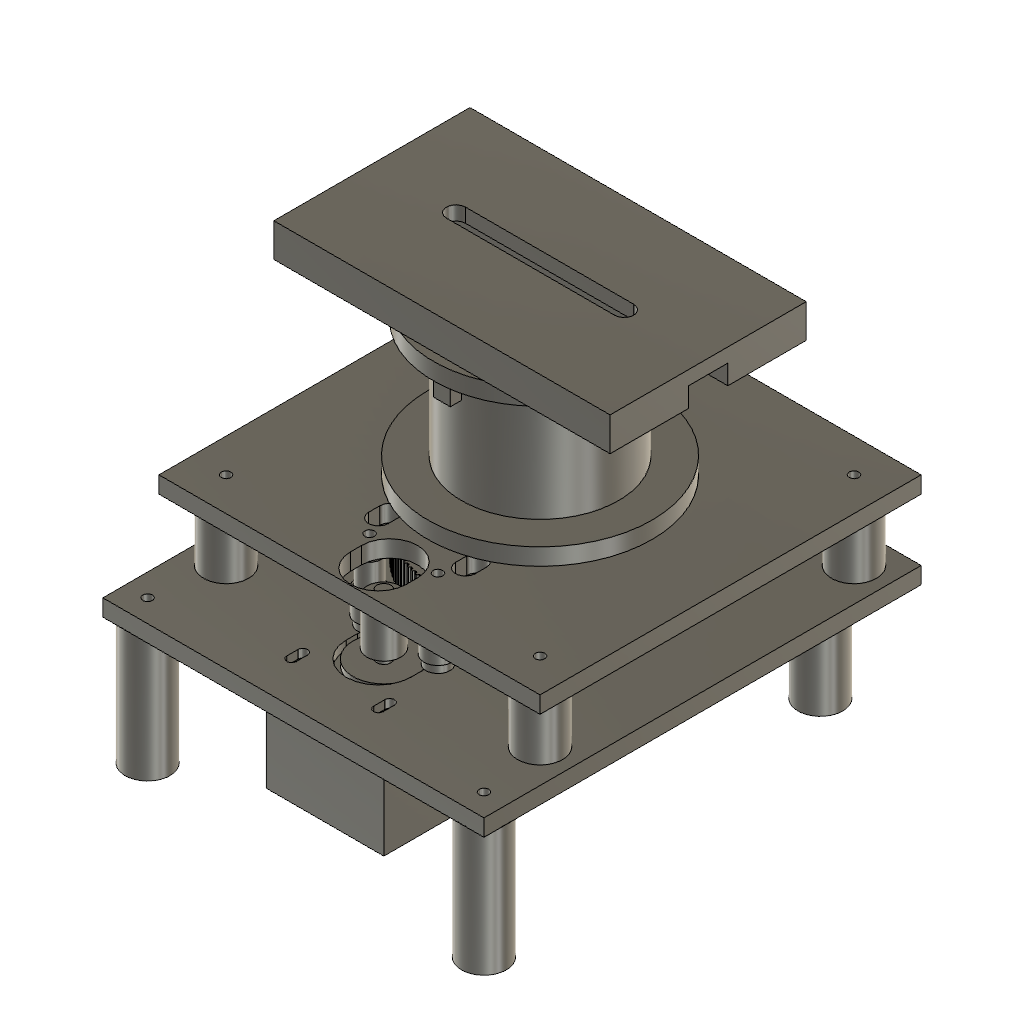
rig (Autodesk Fusion 360 design; units mm, degrees)
part number: 2026-11-04-20-32-03-425
part number: 2026-11-04-21-29-09-329
part number: 2026-11-04-21-29-10-710
part number: 2026-11-04-21-29-11-793
part number: 2026-11-04-21-29-12-270
part number: 2026-11-04-21-29-12-707
part number: 2026-11-04-21-29-14-277
part number: 2026-11-04-21-29-16-163
part number: 2026-11-04-21-29-17-402
part number: 2026-11-04-21-29-18-820
part number: 2026-11-04-21-29-20-301
part number: 2026-11-04-21-29-21-113
part number: 2026-11-04-21-29-36-706
part number: 2026-11-04-21-29-53-141
part number: 2026-11-04-21-29-54-485
part number: 2026-11-04-21-29-56-474
part number: 2026-11-04-21-29-57-771
part number: 2026-11-04-21-29-59-751
part number: 2026-11-04-21-30-00-972
part number: 2026-11-04-21-30-02-569
part number: 2026-11-04-21-30-03-701
part number: 2026-11-04-21-30-04-882
part number: 2026-11-04-21-30-06-087
Autodesk Fusion 360 part; units mm, degrees
(part 1 of 3)
ref_plane "WorkPlane1" through (0, 0, 0) normal (0, 0, 1) x (1, 0, 0) in component "print_bottom_plate"
sketch "Sketch1" plane through (0, 0, 0) normal (0, 0, 1) x (1, 0, 0) in component "print_bottom_plate"
  line L0 (-68, -88) -> (68, -88)
  line L1 (68, -88) -> (68, 68)
  line L2 (68, 68) -> (-68, 68)
  line L3 (-68, 68) -> (-68, -88)
extrude "Extrude1" add sketch "Sketch1" along normal blind 6 makes body 1 in component "print_bottom_plate"
ref_plane "WorkPlane2" through (0, 0, 0) normal (0, 0, 1) x (1, 0, 0) in component "print_bottom_plate"
sketch "Sketch2" plane through (0, 0, 0) normal (0, 0, 1) x (1, 0, 0) in component "print_bottom_plate"
  circle A0 centre (0, 0) radius 22
extrude "Extrude2" cut sketch "Sketch2" along normal blind 6 bodies 1 in component "print_bottom_plate"
ref_plane "WorkPlane3" through (0, 0, 0) normal (0, 0, 1) x (1, 0, 0) in component "print_bottom_plate"
sketch "Sketch3" plane through (0, 0, 0) normal (0, 0, 1) x (1, 0, 0) in component "print_bottom_plate"
  line L0 (-21.5, -79.15) -> (21.5, -79.15)
  line L1 (21.5, -79.15) -> (21.5, -32.15)
  line L2 (21.5, -32.15) -> (-21.5, -32.15)
  line L3 (-21.5, -32.15) -> (-21.5, -79.15)
extrude "Extrude3" cut sketch "Sketch3" along normal blind 3 bodies 1 in component "print_bottom_plate"
ref_plane "WorkPlane4" through (0, 0, 3) normal (0, 0, 1) x (1, 0, 0) in component "print_bottom_plate"
sketch "Sketch4" plane through (0, 0, 3) normal (0, 0, 1) x (1, 0, 0) in component "print_bottom_plate"
  circle A0 centre (0, -57.65) radius 11.5
  circle A1 centre (0, -53.65) radius 11.5
  line L0 (-11.5, -57.65) -> (11.5, -57.65)
  line L1 (11.5, -57.65) -> (11.5, -53.65)
  line L2 (11.5, -53.65) -> (-11.5, -53.65)
  line L3 (-11.5, -53.65) -> (-11.5, -57.65)
extrude "Extrude4" cut sketch "Sketch4" along normal blind 3 bodies 1 in component "print_bottom_plate"
ref_plane "WorkPlane5" through (0, 0, 3) normal (0, 0, 1) x (1, 0, 0) in component "print_bottom_plate"
sketch "Sketch5" plane through (0, 0, 3) normal (0, 0, 1) x (1, 0, 0) in component "print_bottom_plate"
  circle A0 centre (-15.5, -73.15) radius 1.7
  circle A1 centre (-15.5, -69.15) radius 1.7
  line L0 (-17.2, -73.15) -> (-13.8, -73.15)
  line L1 (-13.8, -73.15) -> (-13.8, -69.15)
  line L2 (-13.8, -69.15) -> (-17.2, -69.15)
  line L3 (-17.2, -69.15) -> (-17.2, -73.15)
extrude "Extrude5" cut sketch "Sketch5" along normal blind 3 bodies 1 in component "print_bottom_plate"
ref_plane "WorkPlane6" through (0, 0, 3) normal (0, 0, 1) x (1, 0, 0) in component "print_bottom_plate"
sketch "Sketch6" plane through (0, 0, 3) normal (0, 0, 1) x (1, 0, 0) in component "print_bottom_plate"
  circle A0 centre (-15.5, -42.15) radius 1.7
  circle A1 centre (-15.5, -38.15) radius 1.7
  line L0 (-17.2, -42.15) -> (-13.8, -42.15)
  line L1 (-13.8, -42.15) -> (-13.8, -38.15)
  line L2 (-13.8, -38.15) -> (-17.2, -38.15)
  line L3 (-17.2, -38.15) -> (-17.2, -42.15)
extrude "Extrude6" cut sketch "Sketch6" along normal blind 3 bodies 1 in component "print_bottom_plate"
ref_plane "WorkPlane7" through (0, 0, 3) normal (0, 0, 1) x (1, 0, 0) in component "print_bottom_plate"
sketch "Sketch7" plane through (0, 0, 3) normal (0, 0, 1) x (1, 0, 0) in component "print_bottom_plate"
  circle A0 centre (15.5, -73.15) radius 1.7
  circle A1 centre (15.5, -69.15) radius 1.7
  line L0 (13.8, -73.15) -> (17.2, -73.15)
  line L1 (17.2, -73.15) -> (17.2, -69.15)
  line L2 (17.2, -69.15) -> (13.8, -69.15)
  line L3 (13.8, -69.15) -> (13.8, -73.15)
extrude "Extrude7" cut sketch "Sketch7" along normal blind 3 bodies 1 in component "print_bottom_plate"
ref_plane "WorkPlane8" through (0, 0, 3) normal (0, 0, 1) x (1, 0, 0) in component "print_bottom_plate"
sketch "Sketch8" plane through (0, 0, 3) normal (0, 0, 1) x (1, 0, 0) in component "print_bottom_plate"
  circle A0 centre (15.5, -42.15) radius 1.7
  circle A1 centre (15.5, -38.15) radius 1.7
  line L0 (13.8, -42.15) -> (17.2, -42.15)
  line L1 (17.2, -42.15) -> (17.2, -38.15)
  line L2 (17.2, -38.15) -> (13.8, -38.15)
  line L3 (13.8, -38.15) -> (13.8, -42.15)
extrude "Extrude8" cut sketch "Sketch8" along normal blind 3 bodies 1 in component "print_bottom_plate"
ref_plane "WorkPlane9" through (0, 0, 0) normal (0, 0, 1) x (1, 0, 0) in component "print_bottom_plate"
sketch "Sketch9" plane through (0, 0, 0) normal (0, 0, 1) x (1, 0, 0) in component "print_bottom_plate"
  circle A0 centre (-56, 56) radius 1.7
  circle A1 centre (56, 56) radius 1.7
  circle A2 centre (56, -56) radius 1.7
  circle A3 centre (-56, -56) radius 1.7
  circle A4 centre (-60, -80) radius 1.7
  circle A5 centre (60, -80) radius 1.7
  circle A6 centre (40, 60) radius 1.7
  circle A7 centre (-40, 60) radius 1.7
extrude "Extrude9" cut sketch "Sketch9" along normal blind 6 bodies 1 in component "print_bottom_plate"
ref_plane "WorkPlane10" through (0, 0, 0) normal (0, 0, 1) x (1, 0, 0) in component "print_bottom_plate"
sketch "Sketch10" plane through (0, 0, 0) normal (0, 0, 1) x (1, 0, 0) in component "print_bottom_plate"
  circle A0 centre (-25, -25) radius 2
  circle A1 centre (-25, 25) radius 2
  circle A2 centre (25, -25) radius 2
  circle A3 centre (25, 25) radius 2
extrude "Extrude10" cut sketch "Sketch10" along normal blind 5 bodies 1 in component "print_bottom_plate"
ref_plane "WorkPlane11" through (0, 0, 3) normal (0, 0, 1) x (1, 0, 0) in component "print_bottom_plate"
sketch "Sketch11" plane through (0, 0, 3) normal (0, 0, 1) x (1, 0, 0) in component "print_bottom_plate"
  circle A0 centre (-12.2, -48.6) radius 1.7
  circle A1 centre (12.2, -48.6) radius 1.7
extrude "Extrude11" cut sketch "Sketch11" along normal blind 3 bodies 1 in component "print_bottom_plate"
ref_plane "WorkPlane1" through (0, 0, 28) normal (0, 0, 1) x (1, 0, 0) in component "print_top_plate"
sketch "Sketch1 (2)" plane through (0, 0, 28) normal (0, 0, 1) x (1, 0, 0) in component "print_top_plate"
  line L0 (-68, -68) -> (68, -68)
  line L1 (68, -68) -> (68, 68)
  line L2 (68, 68) -> (-68, 68)
  line L3 (-68, 68) -> (-68, -68)
extrude "Extrude1'" add sketch "Sketch1 (2)" along normal blind 6 separate body makes body 2 in component "print_top_plate"
ref_plane "WorkPlane2" through (0, 0, 28) normal (0, 0, 1) x (1, 0, 0) in component "print_top_plate"
sketch "Sketch2 (2)" plane through (0, 0, 28) normal (0, 0, 1) x (1, 0, 0) in component "print_top_plate"
  circle A0 centre (0, 0) radius 19.5
extrude "Extrude2'" cut sketch "Sketch2 (2)" along normal blind 6 bodies 2 in component "print_top_plate"
ref_plane "WorkPlane3" through (0, 0, 28) normal (0, 0, 1) x (1, 0, 0) in component "print_top_plate"
sketch "Sketch3 (2)" plane through (0, 0, 28) normal (0, 0, 1) x (1, 0, 0) in component "print_top_plate"
  circle A0 centre (-56, 56) radius 1.7
  circle A1 centre (56, 56) radius 1.7
  circle A2 centre (56, -56) radius 1.7
  circle A3 centre (-56, -56) radius 1.7
  circle A4 centre (-12.2, -48.6) radius 1.7
  circle A5 centre (12.2, -48.6) radius 1.7
  circle A6 centre (25.4558, 25.4558) radius 1.7
  circle A7 centre (-25.4558, 25.4558) radius 1.7
  circle A8 centre (-25.4558, -25.4558) radius 1.7
  circle A9 centre (25.4558, -25.4558) radius 1.7
extrude "Extrude3'" cut sketch "Sketch3 (2)" along normal blind 6 bodies 2 in component "print_top_plate"
ref_plane "WorkPlane4" through (0, 0, 28) normal (0, 0, 1) x (1, 0, 0) in component "print_top_plate"
sketch "Sketch4 (2)" plane through (0, 0, 28) normal (0, 0, 1) x (1, 0, 0) in component "print_top_plate"
  circle A0 centre (0, -57.65) radius 10
  circle A1 centre (0, -53.65) radius 10
  line L0 (-10, -57.65) -> (10, -57.65)
  line L1 (10, -57.65) -> (10, -53.65)
  line L2 (10, -53.65) -> (-10, -53.65)
  line L3 (-10, -53.65) -> (-10, -57.65)
extrude "Extrude4'" cut sketch "Sketch4 (2)" along normal blind 6 bodies 2 in component "print_top_plate"
ref_plane "WorkPlane5" through (0, 0, 28) normal (0, 0, 1) x (1, 0, 0) in component "print_top_plate"
sketch "Sketch5 (2)" plane through (0, 0, 28) normal (0, 0, 1) x (1, 0, 0) in component "print_top_plate"
  circle A0 centre (-15.5, -42.15) radius 3.5
  circle A1 centre (-15.5, -38.15) radius 3.5
  line L0 (-19, -42.15) -> (-12, -42.15)
  line L1 (-12, -42.15) -> (-12, -38.15)
  line L2 (-12, -38.15) -> (-19, -38.15)
  line L3 (-19, -38.15) -> (-19, -42.15)
extrude "Extrude5'" cut sketch "Sketch5 (2)" along normal blind 6 bodies 2 in component "print_top_plate"
ref_plane "WorkPlane6" through (0, 0, 28) normal (0, 0, 1) x (1, 0, 0) in component "print_top_plate"
sketch "Sketch6 (2)" plane through (0, 0, 28) normal (0, 0, 1) x (1, 0, 0) in component "print_top_plate"
  circle A0 centre (15.5, -42.15) radius 3.5
  circle A1 centre (15.5, -38.15) radius 3.5
  line L0 (12, -42.15) -> (19, -42.15)
  line L1 (19, -42.15) -> (19, -38.15)
  line L2 (19, -38.15) -> (12, -38.15)
  line L3 (12, -38.15) -> (12, -42.15)
extrude "Extrude6'" cut sketch "Sketch6 (2)" along normal blind 6 bodies 2 in component "print_top_plate"
ref_plane "WorkPlane1" through (0, 0, 6) normal (0, 0, 1) x (1, 0, 0) in component "print_pillar"
sketch "Sketch1 (3)" plane through (0, 0, 6) normal (0, 0, 1) x (1, 0, 0) in component "print_pillar"
  circle A0 centre (-56, 56) radius 8
extrude "Extrude1''" add sketch "Sketch1 (3)" along normal blind 22 separate body makes body 3 in component "print_pillar"
ref_plane "WorkPlane2" through (0, 0, 6) normal (0, 0, 1) x (1, 0, 0) in component "print_pillar"
sketch "Sketch2 (3)" plane through (0, 0, 6) normal (0, 0, 1) x (1, 0, 0) in component "print_pillar"
  circle A0 centre (-56, 56) radius 2
extrude "Extrude2''" cut sketch "Sketch2 (3)" along normal blind 6 bodies 3 in component "print_pillar"
ref_plane "WorkPlane3" through (0, 0, 22) normal (0, 0, 1) x (1, 0, 0) in component "print_pillar"
sketch "Sketch3 (3)" plane through (0, 0, 22) normal (0, 0, 1) x (1, 0, 0) in component "print_pillar"
  circle A0 centre (-56, 56) radius 2
extrude "Extrude3''" cut sketch "Sketch3 (3)" along normal blind 6 bodies 3 in component "print_pillar"
ref_plane "WorkPlane1" through (0, 0, -45) normal (0, 0, 1) x (1, 0, 0) in component "print_foot"
sketch "Sketch1 (4)" plane through (0, 0, -45) normal (0, 0, 1) x (1, 0, 0) in component "print_foot"
  circle A0 centre (-60, -80) radius 8
extrude "Extrude1'''" add sketch "Sketch1 (4)" along normal blind 45 separate body makes body 4 in component "print_foot"
ref_plane "WorkPlane2" through (0, 0, -6) normal (0, 0, 1) x (1, 0, 0) in component "print_foot"
sketch "Sketch2 (4)" plane through (0, 0, -6) normal (0, 0, 1) x (1, 0, 0) in component "print_foot"
  circle A0 centre (-60, -80) radius 2
extrude "Extrude2'''" cut sketch "Sketch2 (4)" along normal blind 6 bodies 4 in component "print_foot"
ref_plane "WorkPlane1" through (0, 0, 34) normal (0, 0, 1) x (1, 0, 0) in component "print_bearing_housing"
sketch "Sketch1 (5)" plane through (0, 0, 34) normal (0, 0, 1) x (1, 0, 0) in component "print_bearing_housing"
  circle A0 centre (0, 0) radius 28
extrude "Extrude1''''" add sketch "Sketch1 (5)" along normal blind 47 separate body makes body 5 in component "print_bearing_housing"
ref_plane "WorkPlane2" through (0, 0, 34) normal (0, 0, 1) x (1, 0, 0) in component "print_bearing_housing"
sketch "Sketch2 (5)" plane through (0, 0, 34) normal (0, 0, 1) x (1, 0, 0) in component "print_bearing_housing"
  circle A0 centre (0, 0) radius 40
extrude "Extrude2''''" add sketch "Sketch2 (5)" along normal blind 6 bodies 5 in component "print_bearing_housing"
ref_plane "WorkPlane3" through (0, 0, 40) normal (0, 0, 1) x (1, 0, 0) in component "print_bearing_housing"
sketch "Sketch3 (4)" plane through (0, 0, 40) normal (0, 0, 1) x (1, 0, 0) in component "print_bearing_housing"
  line L0 (-2, 26) -> (2, 26)
  line L1 (2, 26) -> (2, 35)
  line L2 (2, 35) -> (-2, 35)
  line L3 (-2, 35) -> (-2, 26)
extrude "Extrude3'''" add sketch "Sketch3 (4)" along normal blind 38 bodies 5 in component "print_bearing_housing"
ref_plane "WorkPlane4" through (0, 0, 34) normal (0, 0, 1) x (1, 0, 0) in component "print_bearing_housing"
sketch "Sketch4 (3)" plane through (0, 0, 34) normal (0, 0, 1) x (1, 0, 0) in component "print_bearing_housing"
  circle A0 centre (0, 0) radius 19.5
extrude "Extrude4''" cut sketch "Sketch4 (3)" along normal blind 47 bodies 5 in component "print_bearing_housing"
ref_plane "WorkPlane5" through (0, 0, 34) normal (0, 0, 1) x (1, 0, 0) in component "print_bearing_housing"
sketch "Sketch5 (3)" plane through (0, 0, 34) normal (0, 0, 1) x (1, 0, 0) in component "print_bearing_housing"
  circle A0 centre (0, 0) radius 21.075
extrude "Extrude5''" cut sketch "Sketch5 (3)" along normal blind 7.3 bodies 5 in component "print_bearing_housing"
ref_plane "WorkPlane6" through (0, 0, 34) normal (0, 0, 1) x (1, 0, 0) in component "print_bearing_housing"
sketch "Sketch6 (3)" plane through (0, 0, 34) normal (0, 0, 1) x (1, 0, 0) in component "print_bearing_housing"
  circle A0 centre (0, 0) radius 21.375
extrude "Extrude6''" cut sketch "Sketch6 (3)" along normal blind 0.3 bodies 5 in component "print_bearing_housing"
ref_plane "WorkPlane7" through (0, 0, 74) normal (0, 0, 1) x (1, 0, 0) in component "print_bearing_housing"
sketch "Sketch7 (2)" plane through (0, 0, 74) normal (0, 0, 1) x (1, 0, 0) in component "print_bearing_housing"
  circle A0 centre (0, 0) radius 21.075
extrude "Extrude7'" cut sketch "Sketch7 (2)" along normal blind 7 bodies 5 in component "print_bearing_housing"
ref_plane "WorkPlane8" through (0, 0, 34) normal (0, 0, 1) x (1, 0, 0) in component "print_bearing_housing"
sketch "Sketch8 (2)" plane through (0, 0, 34) normal (0, 0, 1) x (1, 0, 0) in component "print_bearing_housing"
  circle A0 centre (25.4558, 25.4558) radius 2
  circle A1 centre (-25.4558, 25.4558) radius 2
  circle A2 centre (-25.4558, -25.4558) radius 2
  circle A3 centre (25.4558, -25.4558) radius 2
extrude "Extrude8'" cut sketch "Sketch8 (2)" along normal blind 5 bodies 5 in component "print_bearing_housing"
ref_plane "WorkPlane1" through (0, 0, 8.5) normal (0, 0, 1) x (1, 0, 0) in component "print_output_shaft"
sketch "Sketch1 (6)" plane through (0, 0, 8.5) normal (0, 0, 1) x (1, 0, 0) in component "print_output_shaft"
  line L0 (14.4338, 0) -> (7.2169, 12.5)
  line L1 (7.2169, 12.5) -> (-7.2169, 12.5)
  line L2 (-7.2169, 12.5) -> (-14.4338, 0)
  line L3 (-14.4338, 0) -> (-7.2169, -12.5)
  line L4 (-7.2169, -12.5) -> (7.2169, -12.5)
  line L5 (7.2169, -12.5) -> (14.4338, 0)
extrude "Extrude1'''''" add sketch "Sketch1 (6)" along normal blind 25.5 separate body makes body 6 in component "print_output_shaft"
ref_plane "WorkPlane2" through (0, 0, 34) normal (0, 0, 1) x (1, 0, 0) in component "print_output_shaft"
sketch "Sketch2 (6)" plane through (0, 0, 34) normal (0, 0, 1) x (1, 0, 0) in component "print_output_shaft"
  circle A0 centre (0, 0) radius 14.95
extrude "Extrude2'''''" add sketch "Sketch2 (6)" along normal blind 47 bodies 6 in component "print_output_shaft"
ref_plane "WorkPlane3" through (0, 0, 81) normal (0, 0, 1) x (1, 0, 0) in component "print_output_shaft"
sketch "Sketch3 (5)" plane through (0, 0, 81) normal (0, 0, 1) x (1, 0, 0) in component "print_output_shaft"
  circle A0 centre (0, 0) radius 16.5
extrude "Extrude3''''" add sketch "Sketch3 (5)" along normal blind 1 bodies 6 in component "print_output_shaft"
ref_plane "WorkPlane4" through (0, 0, 82) normal (0, 0, 1) x (1, 0, 0) in component "print_output_shaft"
sketch "Sketch4 (4)" plane through (0, 0, 82) normal (0, 0, 1) x (1, 0, 0) in component "print_output_shaft"
  circle A0 centre (0, 0) radius 38
extrude "Extrude4'''" add sketch "Sketch4 (4)" along normal blind 6 bodies 6 in component "print_output_shaft"
ref_plane "WorkPlane5" through (0, 0, 74) normal (0, 0, 1) x (1, 0, 0) in component "print_output_shaft"
sketch "Sketch5 (4)" plane through (0, 0, 74) normal (0, 0, 1) x (1, 0, 0) in component "print_output_shaft"
  line L0 (-3, -35) -> (3, -35)
  line L1 (3, -35) -> (3, -31)
  line L2 (3, -31) -> (-3, -31)
  line L3 (-3, -31) -> (-3, -35)
extrude "Extrude5'''" add sketch "Sketch5 (4)" along normal blind 8 bodies 6 in component "print_output_shaft"
ref_plane "WorkPlane6" through (0, 0, 82) normal (0, 0, 1) x (1, 0, 0) in component "print_output_shaft"
sketch "Sketch6 (4)" plane through (0, 0, 82) normal (0, 0, 1) x (1, 0, 0) in component "print_output_shaft"
  circle A0 centre (-27.7, -16) radius 1.7
  circle A1 centre (27.7, -16) radius 1.7
  circle A2 centre (-27.7, 16) radius 1.7
  circle A3 centre (27.7, 16) radius 1.7
extrude "Extrude6'''" cut sketch "Sketch6 (4)" along normal blind 6 bodies 6 in component "print_output_shaft"
ref_plane "WorkPlane7" through (0, 0, 8.5) normal (0, 0, 1) x (1, 0, 0) in component "print_output_shaft"
sketch "Sketch7 (3)" plane through (0, 0, 8.5) normal (0, 0, 1) x (1, 0, 0) in component "print_output_shaft"
  circle A0 centre (10, 0) radius 2
  circle A1 centre (-5, 8.6603) radius 2
  circle A2 centre (-5, -8.6603) radius 2
extrude "Extrude7''" cut sketch "Sketch7 (3)" along normal blind 6 bodies 6 in component "print_output_shaft"
ref_plane "WorkPlane1" through (0, 0, 3.5) normal (0, 0, 1) x (1, 0, 0) in component "print_magnet_holder"
sketch "Sketch1 (7)" plane through (0, 0, 3.5) normal (0, 0, 1) x (1, 0, 0) in component "print_magnet_holder"
  circle A0 centre (0, 0) radius 20
extrude "Extrude1''''''" add sketch "Sketch1 (7)" along normal blind 4 separate body makes body 7 in component "print_magnet_holder"
ref_plane "WorkPlane2" through (0, 0, 3.5) normal (0, 0, 1) x (1, 0, 0) in component "print_magnet_holder"
sketch "Sketch2 (7)" plane through (0, 0, 3.5) normal (0, 0, 1) x (1, 0, 0) in component "print_magnet_holder"
  circle A0 centre (0, 0) radius 3.05
extrude "Extrude2''''''" cut sketch "Sketch2 (7)" along normal blind 2.5 bodies 7 in component "print_magnet_holder"
ref_plane "WorkPlane3" through (0, 0, 3.5) normal (0, 0, 1) x (1, 0, 0) in component "print_magnet_holder"
sketch "Sketch3 (6)" plane through (0, 0, 3.5) normal (0, 0, 1) x (1, 0, 0) in component "print_magnet_holder"
  circle A0 centre (10, 0) radius 1.7
  circle A1 centre (-5, 8.6603) radius 1.7
  circle A2 centre (-5, -8.6603) radius 1.7
extrude "Extrude3'''''" cut sketch "Sketch3 (6)" along normal blind 4 bodies 7 in component "print_magnet_holder"
ref_plane "WorkPlane4" through (0, 0, 3.5) normal (0, 0, 1) x (1, 0, 0) in component "print_magnet_holder"
sketch "Sketch4 (5)" plane through (0, 0, 3.5) normal (0, 0, 1) x (1, 0, 0) in component "print_magnet_holder"
  circle A0 centre (10, 0) radius 3
  circle A1 centre (-5, 8.6603) radius 3
  circle A2 centre (-5, -8.6603) radius 3
extrude "Extrude4''''" cut sketch "Sketch4 (5)" along normal blind 2 bodies 7 in component "print_magnet_holder"
ref_plane "WorkPlane1" through (0, 0, 88) normal (0, 0, 1) x (1, 0, 0) in component "print_camera_plate"
sketch "Sketch1 (8)" plane through (0, 0, 88) normal (0, 0, 1) x (1, 0, 0) in component "print_camera_plate"
  line L0 (-60, -35) -> (60, -35)
  line L1 (60, -35) -> (60, 35)
  line L2 (60, 35) -> (-60, 35)
  line L3 (-60, 35) -> (-60, -35)
extrude "Extrude1'''''''" add sketch "Sketch1 (8)" along normal blind 12 separate body makes body 8 in component "print_camera_plate"
ref_plane "WorkPlane2" through (0, 0, 88) normal (0, 0, 1) x (1, 0, 0) in component "print_camera_plate"
sketch "Sketch2 (8)" plane through (0, 0, 88) normal (0, 0, 1) x (1, 0, 0) in component "print_camera_plate"
  circle A0 centre (-30, 0) radius 3.4
  circle A1 centre (30, 0) radius 3.4
  line L0 (-30, -3.4) -> (30, -3.4)
  line L1 (30, -3.4) -> (30, 3.4)
  line L2 (30, 3.4) -> (-30, 3.4)
  line L3 (-30, 3.4) -> (-30, -3.4)
extrude "Extrude2'''''''" cut sketch "Sketch2 (8)" along normal blind 12 bodies 8 in component "print_camera_plate"
ref_plane "WorkPlane3" through (0, 0, 88) normal (0, 0, 1) x (1, 0, 0) in component "print_camera_plate"
sketch "Sketch3 (7)" plane through (0, 0, 88) normal (0, 0, 1) x (1, 0, 0) in component "print_camera_plate"
  line L0 (-60, -7) -> (60, -7)
  line L1 (60, -7) -> (60, 7)
  line L2 (60, 7) -> (-60, 7)
  line L3 (-60, 7) -> (-60, -7)
extrude "Extrude3''''''" cut sketch "Sketch3 (7)" along normal blind 7 bodies 8 in component "print_camera_plate"
ref_plane "WorkPlane4" through (0, 0, 88) normal (0, 0, 1) x (1, 0, 0) in component "print_camera_plate"
sketch "Sketch4 (6)" plane through (0, 0, 88) normal (0, 0, 1) x (1, 0, 0) in component "print_camera_plate"
  circle A0 centre (-27.7, -16) radius 2
  circle A1 centre (27.7, -16) radius 2
  circle A2 centre (-27.7, 16) radius 2
  circle A3 centre (27.7, 16) radius 2
extrude "Extrude4'''''" cut sketch "Sketch4 (6)" along normal blind 6 bodies 8 in component "print_camera_plate"
ref_plane "WorkPlane1" through (0, 0, -8) normal (0, 0, 1) x (1, 0, 0) in component "print_sensor_tray"
sketch "Sketch1 (9)" plane through (0, 0, -8) normal (0, 0, 1) x (1, 0, 0) in component "print_sensor_tray"
  line L0 (-30, -30) -> (30, -30)
  line L1 (30, -30) -> (30, 30)
  line L2 (30, 30) -> (-30, 30)
  line L3 (-30, 30) -> (-30, -30)
extrude "Extrude1''''''''" add sketch "Sketch1 (9)" along normal blind 3 separate body makes body 9 in component "print_sensor_tray"
ref_plane "WorkPlane2" through (0, 0, -5) normal (0, 0, 1) x (1, 0, 0) in component "print_sensor_tray"
sketch "Sketch2 (9)" plane through (0, 0, -5) normal (0, 0, 1) x (1, 0, 0) in component "print_sensor_tray"
  circle A0 centre (0, 0) radius 15
extrude "Extrude2''''''''" add sketch "Sketch2 (9)" along normal blind 4 bodies 9 in component "print_sensor_tray"
ref_plane "WorkPlane3" through (0, 0, -5) normal (0, 0, 1) x (1, 0, 0) in component "print_sensor_tray"
sketch "Sketch3 (8)" plane through (0, 0, -5) normal (0, 0, 1) x (1, 0, 0) in component "print_sensor_tray"
  circle A0 centre (-25, -25) radius 4
  circle A1 centre (-25, 25) radius 4
  circle A2 centre (25, -25) radius 4
  circle A3 centre (25, 25) radius 4
extrude "Extrude3'''''''" add sketch "Sketch3 (8)" along normal blind 5 bodies 9 in component "print_sensor_tray"
ref_plane "WorkPlane4" through (0, 0, -8) normal (0, 0, 1) x (1, 0, 0) in component "print_sensor_tray"
sketch "Sketch4 (7)" plane through (0, 0, -8) normal (0, 0, 1) x (1, 0, 0) in component "print_sensor_tray"
  circle A0 centre (-25, -25) radius 1.7
  circle A1 centre (-25, 25) radius 1.7
  circle A2 centre (25, -25) radius 1.7
  circle A3 centre (25, 25) radius 1.7
extrude "Extrude4''''''" cut sketch "Sketch4 (7)" along normal blind 8 bodies 9 in component "print_sensor_tray"
ref_plane "WorkPlane1" through (0, 0, 18.5) normal (0, 0, 1) x (1, 0, 0) in component "print_spacer"
sketch "Sketch1 (10)" plane through (0, 0, 18.5) normal (0, 0, 1) x (1, 0, 0) in component "print_spacer"
  circle A0 centre (0, 0) radius 16.5
extrude "Extrude1'''''''''" add sketch "Sketch1 (10)" along normal blind 15.5 separate body makes body 10 in component "print_spacer"
ref_plane "WorkPlane2" through (0, 0, 18.5) normal (0, 0, 1) x (1, 0, 0) in component "print_spacer"
sketch "Sketch2 (10)" plane through (0, 0, 18.5) normal (0, 0, 1) x (1, 0, 0) in component "print_spacer"
  line L0 (14.607, 0) -> (7.3035, 12.65)
  line L1 (7.3035, 12.65) -> (-7.3035, 12.65)
  line L2 (-7.3035, 12.65) -> (-14.607, 0)
  line L3 (-14.607, 0) -> (-7.3035, -12.65)
  line L4 (-7.3035, -12.65) -> (7.3035, -12.65)
  line L5 (7.3035, -12.65) -> (14.607, 0)
extrude "Extrude2'''''''''" cut sketch "Sketch2 (10)" along normal blind 15.5 bodies 10 in component "print_spacer"
ref_plane "WorkPlane1" through (0, 0, 7.5) normal (0, 0, 1) x (1, 0, 0) in component "print_pulley_120T"
sketch "Sketch1 (11)" plane through (0, 0, 7.5) normal (0, 0, 1) x (1, 0, 0) in component "print_pulley_120T"
  line L0 (37.9374, -0.66) -> (37.3977, -0.4554)
  line L1 (37.3977, -0.4554) -> (37.2306, -0.2267)
  line L2 (37.2306, -0.2267) -> (37.1832, 0)
  line L3 (37.1832, 0) -> (37.2306, 0.2267)
  line L4 (37.2306, 0.2267) -> (37.3977, 0.4554)
  line L5 (37.3977, 0.4554) -> (37.9374, 0.66)
  line L6 (37.9374, 0.66) -> (37.92, 1.3264)
  line L7 (37.92, 1.3264) -> (37.3702, 1.5025)
  line L8 (37.3702, 1.5025) -> (37.1914, 1.7221)
  line L9 (37.1914, 1.7221) -> (37.1322, 1.946)
  line L10 (37.1322, 1.946) -> (37.1677, 2.1749)
  line L11 (37.1677, 2.1749) -> (37.3226, 2.412)
  line L12 (37.3226, 2.412) -> (37.8509, 2.6446)
  line L13 (37.8509, 2.6446) -> (37.7986, 3.3092)
  line L14 (37.7986, 3.3092) -> (37.2404, 3.4562)
  line L15 (37.2404, 3.4562) -> (37.0503, 3.6662)
  line L16 (37.0503, 3.6662) -> (36.9795, 3.8867)
  line L17 (36.9795, 3.8867) -> (37.0029, 4.1171)
  line L18 (37.0029, 4.1171) -> (37.1452, 4.362)
  line L19 (37.1452, 4.362) -> (37.6606, 4.6219)
  line L20 (37.6606, 4.6219) -> (37.5736, 5.2829)
  line L21 (37.5736, 5.2829) -> (37.0085, 5.4005)
  line L22 (37.0085, 5.4005) -> (36.8077, 5.6003)
  line L23 (36.8077, 5.6003) -> (36.7254, 5.8167)
  line L24 (36.7254, 5.8167) -> (36.7367, 6.048)
  line L25 (36.7367, 6.048) -> (36.866, 6.3001)
  line L26 (36.866, 6.3001) -> (37.3671, 6.5866)
  line L27 (37.3671, 6.5866) -> (37.2456, 7.2421)
  line L28 (37.2456, 7.2421) -> (36.6751, 7.33)
  line L29 (36.6751, 7.33) -> (36.4641, 7.519)
  line L30 (36.4641, 7.519) -> (36.3706, 7.7308)
  line L31 (36.3706, 7.7308) -> (36.3699, 7.9624)
  line L32 (36.3699, 7.9624) -> (36.4858, 8.2208)
  line L33 (36.4858, 8.2208) -> (36.9712, 8.5332)
  line L34 (36.9712, 8.5332) -> (36.8156, 9.1815)
  line L35 (36.8156, 9.1815) -> (36.2412, 9.2394)
  line L36 (36.2412, 9.2394) -> (36.0206, 9.417)
  line L37 (36.0206, 9.417) -> (35.9162, 9.6237)
  line L38 (35.9162, 9.6237) -> (35.9033, 9.8549)
  line L39 (35.9033, 9.8549) -> (36.0055, 10.1191)
  line L40 (36.0055, 10.1191) -> (36.4739, 10.4564)
  line L41 (36.4739, 10.4564) -> (36.2846, 11.0956)
  line L42 (36.2846, 11.0956) -> (35.708, 11.1234)
  line L43 (35.708, 11.1234) -> (35.4784, 11.2893)
  line L44 (35.4784, 11.2893) -> (35.3633, 11.4902)
  line L45 (35.3633, 11.4902) -> (35.3383, 11.7204)
  line L46 (35.3383, 11.7204) -> (35.4266, 11.9896)
  line L47 (35.4266, 11.9896) -> (35.8767, 12.351)
  line L48 (35.8767, 12.351) -> (35.6542, 12.9794)
  line L49 (35.6542, 12.9794) -> (35.0769, 12.977)
  line L50 (35.0769, 12.977) -> (34.839, 13.1306)
  line L51 (34.839, 13.1306) -> (34.7135, 13.3253)
  line L52 (34.7135, 13.3253) -> (34.6765, 13.5539)
  line L53 (34.6765, 13.5539) -> (34.7505, 13.8273)
  line L54 (34.7505, 13.8273) -> (35.1811, 14.2117)
  line L55 (35.1811, 14.2117) -> (34.926, 14.8276)
  line L56 (34.926, 14.8276) -> (34.3497, 14.795)
  line L57 (34.3497, 14.795) -> (34.104, 14.936)
  line L58 (34.104, 14.936) -> (33.9685, 15.1238)
  line L59 (33.9685, 15.1238) -> (33.9196, 15.3501)
  line L60 (33.9196, 15.3501) -> (33.9792, 15.627)
  line L61 (33.9792, 15.627) -> (34.3891, 16.0335)
  line L62 (34.3891, 16.0335) -> (34.1021, 16.6352)
  line L63 (34.1021, 16.6352) -> (33.5283, 16.5724)
  line L64 (33.5283, 16.5724) -> (33.2756, 16.7004)
  line L65 (33.2756, 16.7004) -> (33.1305, 16.8808)
  line L66 (33.1305, 16.8808) -> (33.0698, 17.1043)
  line L67 (33.0698, 17.1043) -> (33.1148, 17.3839)
  line L68 (33.1148, 17.3839) -> (33.5029, 17.8113)
  line L69 (33.5029, 17.8113) -> (33.1848, 18.3972)
  line L70 (33.1848, 18.3972) -> (32.615, 18.3045)
  line L71 (32.615, 18.3045) -> (32.3559, 18.419)
  line L72 (32.3559, 18.419) -> (32.2016, 18.5916)
  line L73 (32.2016, 18.5916) -> (32.1293, 18.8116)
  line L74 (32.1293, 18.8116) -> (32.1596, 19.0932)
  line L75 (32.1596, 19.0932) -> (32.5248, 19.5403)
  line L76 (32.5248, 19.5403) -> (32.1765, 20.1087)
  line L77 (32.1765, 20.1087) -> (31.6123, 19.9863)
  line L78 (31.6123, 19.9863) -> (31.3476, 20.0871)
  line L79 (31.3476, 20.0871) -> (31.1844, 20.2514)
  line L80 (31.1844, 20.2514) -> (31.1007, 20.4673)
  line L81 (31.1007, 20.4673) -> (31.1163, 20.7501)
  line L82 (31.1163, 20.7501) -> (31.4576, 21.2157)
  line L83 (31.4576, 21.2157) -> (31.08, 21.7651)
  line L84 (31.08, 21.7651) -> (30.523, 21.6134)
  line L85 (30.523, 21.6134) -> (30.2534, 21.7002)
  line L86 (30.2534, 21.7002) -> (30.0818, 21.8557)
  line L87 (30.0818, 21.8557) -> (29.9869, 22.067)
  line L88 (29.9869, 22.067) -> (29.9877, 22.3502)
  line L89 (29.9877, 22.3502) -> (30.3041, 22.833)
  line L90 (30.3041, 22.833) -> (29.8983, 23.3619)
  line L91 (29.8983, 23.3619) -> (29.35, 23.1812)
  line L92 (29.35, 23.1812) -> (29.0762, 23.2538)
  line L93 (29.0762, 23.2538) -> (28.8968, 23.4001)
  line L94 (28.8968, 23.4001) -> (28.7909, 23.6061)
  line L95 (28.7909, 23.6061) -> (28.7769, 23.889)
  line L96 (28.7769, 23.889) -> (29.0676, 24.3877)
  line L97 (29.0676, 24.3877) -> (28.6346, 24.8947)
  line L98 (28.6346, 24.8947) -> (28.0966, 24.6855)
  line L99 (28.0966, 24.6855) -> (27.8194, 24.7437)
  line L100 (27.8194, 24.7437) -> (27.6325, 24.8804)
  line L101 (27.6325, 24.8804) -> (27.516, 25.0806)
  line L102 (27.516, 25.0806) -> (27.4872, 25.3623)
  line L103 (27.4872, 25.3623) -> (27.7514, 25.8756)
  line L104 (27.7514, 25.8756) -> (27.2925, 26.3592)
  line L105 (27.2925, 26.3592) -> (26.7661, 26.1221)
  line L106 (26.7661, 26.1221) -> (26.4863, 26.1657)
  line L107 (26.4863, 26.1657) -> (26.2925, 26.2925)
  line L108 (26.2925, 26.2925) -> (26.1657, 26.4863)
  line L109 (26.1657, 26.4863) -> (26.1221, 26.7661)
  line L110 (26.1221, 26.7661) -> (26.3592, 27.2925)
  line L111 (26.3592, 27.2925) -> (25.8756, 27.7514)
  line L112 (25.8756, 27.7514) -> (25.3623, 27.4872)
  line L113 (25.3623, 27.4872) -> (25.0806, 27.516)
  line L114 (25.0806, 27.516) -> (24.8804, 27.6325)
  line L115 (24.8804, 27.6325) -> (24.7437, 27.8194)
  line L116 (24.7437, 27.8194) -> (24.6855, 28.0966)
  line L117 (24.6855, 28.0966) -> (24.8947, 28.6346)
  line L118 (24.8947, 28.6346) -> (24.3877, 29.0676)
  line L119 (24.3877, 29.0676) -> (23.889, 28.7769)
  line L120 (23.889, 28.7769) -> (23.6061, 28.7909)
  line L121 (23.6061, 28.7909) -> (23.4001, 28.8968)
  line L122 (23.4001, 28.8968) -> (23.2538, 29.0762)
  line L123 (23.2538, 29.0762) -> (23.1812, 29.35)
  line L124 (23.1812, 29.35) -> (23.3619, 29.8983)
  line L125 (23.3619, 29.8983) -> (22.833, 30.3041)
  line L126 (22.833, 30.3041) -> (22.3502, 29.9877)
  line L127 (22.3502, 29.9877) -> (22.067, 29.9869)
  line L128 (22.067, 29.9869) -> (21.8557, 30.0818)
  line L129 (21.8557, 30.0818) -> (21.7002, 30.2534)
  line L130 (21.7002, 30.2534) -> (21.6134, 30.523)
  line L131 (21.6134, 30.523) -> (21.7651, 31.08)
  line L132 (21.7651, 31.08) -> (21.2157, 31.4576)
  line L133 (21.2157, 31.4576) -> (20.7501, 31.1163)
  line L134 (20.7501, 31.1163) -> (20.4673, 31.1007)
  line L135 (20.4673, 31.1007) -> (20.2514, 31.1844)
  line L136 (20.2514, 31.1844) -> (20.0871, 31.3476)
  line L137 (20.0871, 31.3476) -> (19.9863, 31.6123)
  line L138 (19.9863, 31.6123) -> (20.1087, 32.1765)
  line L139 (20.1087, 32.1765) -> (19.5403, 32.5248)
  line L140 (19.5403, 32.5248) -> (19.0932, 32.1596)
  line L141 (19.0932, 32.1596) -> (18.8116, 32.1293)
  line L142 (18.8116, 32.1293) -> (18.5916, 32.2016)
  line L143 (18.5916, 32.2016) -> (18.419, 32.3559)
  line L144 (18.419, 32.3559) -> (18.3045, 32.615)
  line L145 (18.3045, 32.615) -> (18.3972, 33.1848)
  line L146 (18.3972, 33.1848) -> (17.8113, 33.5029)
  line L147 (17.8113, 33.5029) -> (17.3839, 33.1148)
  line L148 (17.3839, 33.1148) -> (17.1043, 33.0698)
  line L149 (17.1043, 33.0698) -> (16.8808, 33.1305)
  line L150 (16.8808, 33.1305) -> (16.7004, 33.2756)
  line L151 (16.7004, 33.2756) -> (16.5724, 33.5283)
  line L152 (16.5724, 33.5283) -> (16.6352, 34.1021)
  line L153 (16.6352, 34.1021) -> (16.0335, 34.3891)
  line L154 (16.0335, 34.3891) -> (15.627, 33.9792)
  line L155 (15.627, 33.9792) -> (15.3501, 33.9196)
  line L156 (15.3501, 33.9196) -> (15.1238, 33.9685)
  line L157 (15.1238, 33.9685) -> (14.936, 34.104)
  line L158 (14.936, 34.104) -> (14.795, 34.3497)
  line L159 (14.795, 34.3497) -> (14.8276, 34.926)
  line L160 (14.8276, 34.926) -> (14.2117, 35.1811)
  line L161 (14.2117, 35.1811) -> (13.8273, 34.7505)
  line L162 (13.8273, 34.7505) -> (13.5539, 34.6765)
  line L163 (13.5539, 34.6765) -> (13.3253, 34.7135)
  line L164 (13.3253, 34.7135) -> (13.1306, 34.839)
  line L165 (13.1306, 34.839) -> (12.977, 35.0769)
  line L166 (12.977, 35.0769) -> (12.9794, 35.6542)
  line L167 (12.9794, 35.6542) -> (12.351, 35.8767)
  line L168 (12.351, 35.8767) -> (11.9896, 35.4266)
  line L169 (11.9896, 35.4266) -> (11.7204, 35.3383)
  line L170 (11.7204, 35.3383) -> (11.4902, 35.3633)
  line L171 (11.4902, 35.3633) -> (11.2893, 35.4784)
  line L172 (11.2893, 35.4784) -> (11.1234, 35.708)
  line L173 (11.1234, 35.708) -> (11.0956, 36.2846)
  line L174 (11.0956, 36.2846) -> (10.4564, 36.4739)
  line L175 (10.4564, 36.4739) -> (10.1191, 36.0055)
  line L176 (10.1191, 36.0055) -> (9.8549, 35.9033)
  line L177 (9.8549, 35.9033) -> (9.6237, 35.9162)
  line L178 (9.6237, 35.9162) -> (9.417, 36.0206)
  line L179 (9.417, 36.0206) -> (9.2394, 36.2412)
  line L180 (9.2394, 36.2412) -> (9.1815, 36.8156)
  line L181 (9.1815, 36.8156) -> (8.5332, 36.9712)
  line L182 (8.5332, 36.9712) -> (8.2208, 36.4858)
  line L183 (8.2208, 36.4858) -> (7.9624, 36.3699)
  line L184 (7.9624, 36.3699) -> (7.7308, 36.3706)
  line L185 (7.7308, 36.3706) -> (7.519, 36.4641)
  line L186 (7.519, 36.4641) -> (7.33, 36.6751)
  line L187 (7.33, 36.6751) -> (7.2421, 37.2456)
  line L188 (7.2421, 37.2456) -> (6.5866, 37.3671)
  line L189 (6.5866, 37.3671) -> (6.3001, 36.866)
  line L190 (6.3001, 36.866) -> (6.048, 36.7367)
  line L191 (6.048, 36.7367) -> (5.8167, 36.7254)
  line L192 (5.8167, 36.7254) -> (5.6003, 36.8077)
  line L193 (5.6003, 36.8077) -> (5.4005, 37.0085)
  line L194 (5.4005, 37.0085) -> (5.2829, 37.5736)
  line L195 (5.2829, 37.5736) -> (4.6219, 37.6606)
  line L196 (4.6219, 37.6606) -> (4.362, 37.1452)
  line L197 (4.362, 37.1452) -> (4.1171, 37.0029)
  line L198 (4.1171, 37.0029) -> (3.8867, 36.9795)
  line L199 (3.8867, 36.9795) -> (3.6662, 37.0503)
  line L200 (3.6662, 37.0503) -> (3.4562, 37.2404)
  line L201 (3.4562, 37.2404) -> (3.3092, 37.7986)
  line L202 (3.3092, 37.7986) -> (2.6446, 37.8509)
  line L203 (2.6446, 37.8509) -> (2.412, 37.3226)
  line L204 (2.412, 37.3226) -> (2.1749, 37.1677)
  line L205 (2.1749, 37.1677) -> (1.946, 37.1322)
  line L206 (1.946, 37.1322) -> (1.7221, 37.1914)
  line L207 (1.7221, 37.1914) -> (1.5025, 37.3702)
  line L208 (1.5025, 37.3702) -> (1.3264, 37.92)
  line L209 (1.3264, 37.92) -> (0.66, 37.9374)
  line L210 (0.66, 37.9374) -> (0.4554, 37.3977)
  line L211 (0.4554, 37.3977) -> (0.2267, 37.2306)
  line L212 (0.2267, 37.2306) -> (0, 37.1832)
  line L213 (0, 37.1832) -> (-0.2267, 37.2306)
  line L214 (-0.2267, 37.2306) -> (-0.4554, 37.3977)
  line L215 (-0.4554, 37.3977) -> (-0.66, 37.9374)
  line L216 (-0.66, 37.9374) -> (-1.3264, 37.92)
  line L217 (-1.3264, 37.92) -> (-1.5025, 37.3702)
  line L218 (-1.5025, 37.3702) -> (-1.7221, 37.1914)
  line L219 (-1.7221, 37.1914) -> (-1.946, 37.1322)
  line L220 (-1.946, 37.1322) -> (-2.1749, 37.1677)
  line L221 (-2.1749, 37.1677) -> (-2.412, 37.3226)
  line L222 (-2.412, 37.3226) -> (-2.6446, 37.8509)
  line L223 (-2.6446, 37.8509) -> (-3.3092, 37.7986)
  line L224 (-3.3092, 37.7986) -> (-3.4562, 37.2404)
  line L225 (-3.4562, 37.2404) -> (-3.6662, 37.0503)
  line L226 (-3.6662, 37.0503) -> (-3.8867, 36.9795)
  line L227 (-3.8867, 36.9795) -> (-4.1171, 37.0029)
  line L228 (-4.1171, 37.0029) -> (-4.362, 37.1452)
  line L229 (-4.362, 37.1452) -> (-4.6219, 37.6606)
  line L230 (-4.6219, 37.6606) -> (-5.2829, 37.5736)
  line L231 (-5.2829, 37.5736) -> (-5.4005, 37.0085)
  line L232 (-5.4005, 37.0085) -> (-5.6003, 36.8077)
  line L233 (-5.6003, 36.8077) -> (-5.8167, 36.7254)
  line L234 (-5.8167, 36.7254) -> (-6.048, 36.7367)
  line L235 (-6.048, 36.7367) -> (-6.3001, 36.866)
  line L236 (-6.3001, 36.866) -> (-6.5866, 37.3671)
  line L237 (-6.5866, 37.3671) -> (-7.2421, 37.2456)
  line L238 (-7.2421, 37.2456) -> (-7.33, 36.6751)
  line L239 (-7.33, 36.6751) -> (-7.519, 36.4641)
  line L240 (-7.519, 36.4641) -> (-7.7308, 36.3706)
  line L241 (-7.7308, 36.3706) -> (-7.9624, 36.3699)
  line L242 (-7.9624, 36.3699) -> (-8.2208, 36.4858)
  line L243 (-8.2208, 36.4858) -> (-8.5332, 36.9712)
  line L244 (-8.5332, 36.9712) -> (-9.1815, 36.8156)
  line L245 (-9.1815, 36.8156) -> (-9.2394, 36.2412)
  line L246 (-9.2394, 36.2412) -> (-9.417, 36.0206)
  line L247 (-9.417, 36.0206) -> (-9.6237, 35.9162)
  line L248 (-9.6237, 35.9162) -> (-9.8549, 35.9033)
  line L249 (-9.8549, 35.9033) -> (-10.1191, 36.0055)
  line L250 (-10.1191, 36.0055) -> (-10.4564, 36.4739)
  line L251 (-10.4564, 36.4739) -> (-11.0956, 36.2846)
  line L252 (-11.0956, 36.2846) -> (-11.1234, 35.708)
  line L253 (-11.1234, 35.708) -> (-11.2893, 35.4784)
  line L254 (-11.2893, 35.4784) -> (-11.4902, 35.3633)
  line L255 (-11.4902, 35.3633) -> (-11.7204, 35.3383)
  line L256 (-11.7204, 35.3383) -> (-11.9896, 35.4266)
  line L257 (-11.9896, 35.4266) -> (-12.351, 35.8767)
  line L258 (-12.351, 35.8767) -> (-12.9794, 35.6542)
  line L259 (-12.9794, 35.6542) -> (-12.977, 35.0769)
  line L260 (-12.977, 35.0769) -> (-13.1306, 34.839)
  line L261 (-13.1306, 34.839) -> (-13.3253, 34.7135)
  line L262 (-13.3253, 34.7135) -> (-13.5539, 34.6765)
  line L263 (-13.5539, 34.6765) -> (-13.8273, 34.7505)
  line L264 (-13.8273, 34.7505) -> (-14.2117, 35.1811)
  line L265 (-14.2117, 35.1811) -> (-14.8276, 34.926)
  line L266 (-14.8276, 34.926) -> (-14.795, 34.3497)
  line L267 (-14.795, 34.3497) -> (-14.936, 34.104)
  line L268 (-14.936, 34.104) -> (-15.1238, 33.9685)
  line L269 (-15.1238, 33.9685) -> (-15.3501, 33.9196)
  line L270 (-15.3501, 33.9196) -> (-15.627, 33.9792)
  line L271 (-15.627, 33.9792) -> (-16.0335, 34.3891)
  line L272 (-16.0335, 34.3891) -> (-16.6352, 34.1021)
  line L273 (-16.6352, 34.1021) -> (-16.5724, 33.5283)
  line L274 (-16.5724, 33.5283) -> (-16.7004, 33.2756)
  line L275 (-16.7004, 33.2756) -> (-16.8808, 33.1305)
  line L276 (-16.8808, 33.1305) -> (-17.1043, 33.0698)
  line L277 (-17.1043, 33.0698) -> (-17.3839, 33.1148)
  line L278 (-17.3839, 33.1148) -> (-17.8113, 33.5029)
  line L279 (-17.8113, 33.5029) -> (-18.3972, 33.1848)
  line L280 (-18.3972, 33.1848) -> (-18.3045, 32.615)
  line L281 (-18.3045, 32.615) -> (-18.419, 32.3559)
  line L282 (-18.419, 32.3559) -> (-18.5916, 32.2016)
  line L283 (-18.5916, 32.2016) -> (-18.8116, 32.1293)
  line L284 (-18.8116, 32.1293) -> (-19.0932, 32.1596)
  line L285 (-19.0932, 32.1596) -> (-19.5403, 32.5248)
  line L286 (-19.5403, 32.5248) -> (-20.1087, 32.1765)
  line L287 (-20.1087, 32.1765) -> (-19.9863, 31.6123)
  line L288 (-19.9863, 31.6123) -> (-20.0871, 31.3476)
  line L289 (-20.0871, 31.3476) -> (-20.2514, 31.1844)
  line L290 (-20.2514, 31.1844) -> (-20.4673, 31.1007)
  line L291 (-20.4673, 31.1007) -> (-20.7501, 31.1163)
  line L292 (-20.7501, 31.1163) -> (-21.2157, 31.4576)
  line L293 (-21.2157, 31.4576) -> (-21.7651, 31.08)
  line L294 (-21.7651, 31.08) -> (-21.6134, 30.523)
  line L295 (-21.6134, 30.523) -> (-21.7002, 30.2534)
  line L296 (-21.7002, 30.2534) -> (-21.8557, 30.0818)
  line L297 (-21.8557, 30.0818) -> (-22.067, 29.9869)
  line L298 (-22.067, 29.9869) -> (-22.3502, 29.9877)
  line L299 (-22.3502, 29.9877) -> (-22.833, 30.3041)
  line L300 (-22.833, 30.3041) -> (-23.3619, 29.8983)
  line L301 (-23.3619, 29.8983) -> (-23.1812, 29.35)
  line L302 (-23.1812, 29.35) -> (-23.2538, 29.0762)
  line L303 (-23.2538, 29.0762) -> (-23.4001, 28.8968)
  line L304 (-23.4001, 28.8968) -> (-23.6061, 28.7909)
  line L305 (-23.6061, 28.7909) -> (-23.889, 28.7769)
  line L306 (-23.889, 28.7769) -> (-24.3877, 29.0676)
  line L307 (-24.3877, 29.0676) -> (-24.8947, 28.6346)
  line L308 (-24.8947, 28.6346) -> (-24.6855, 28.0966)
  line L309 (-24.6855, 28.0966) -> (-24.7437, 27.8194)
  line L310 (-24.7437, 27.8194) -> (-24.8804, 27.6325)
  line L311 (-24.8804, 27.6325) -> (-25.0806, 27.516)
  line L312 (-25.0806, 27.516) -> (-25.3623, 27.4872)
  line L313 (-25.3623, 27.4872) -> (-25.8756, 27.7514)
  line L314 (-25.8756, 27.7514) -> (-26.3592, 27.2925)
  line L315 (-26.3592, 27.2925) -> (-26.1221, 26.7661)
  line L316 (-26.1221, 26.7661) -> (-26.1657, 26.4863)
  line L317 (-26.1657, 26.4863) -> (-26.2925, 26.2925)
  line L318 (-26.2925, 26.2925) -> (-26.4863, 26.1657)
  line L319 (-26.4863, 26.1657) -> (-26.7661, 26.1221)
  line L320 (-26.7661, 26.1221) -> (-27.2925, 26.3592)
  line L321 (-27.2925, 26.3592) -> (-27.7514, 25.8756)
  line L322 (-27.7514, 25.8756) -> (-27.4872, 25.3623)
  line L323 (-27.4872, 25.3623) -> (-27.516, 25.0806)
  line L324 (-27.516, 25.0806) -> (-27.6325, 24.8804)
  line L325 (-27.6325, 24.8804) -> (-27.8194, 24.7437)
  line L326 (-27.8194, 24.7437) -> (-28.0966, 24.6855)
  line L327 (-28.0966, 24.6855) -> (-28.6346, 24.8947)
  line L328 (-28.6346, 24.8947) -> (-29.0676, 24.3877)
  line L329 (-29.0676, 24.3877) -> (-28.7769, 23.889)
  line L330 (-28.7769, 23.889) -> (-28.7909, 23.6061)
  line L331 (-28.7909, 23.6061) -> (-28.8968, 23.4001)
  line L332 (-28.8968, 23.4001) -> (-29.0762, 23.2538)
  line L333 (-29.0762, 23.2538) -> (-29.35, 23.1812)
  line L334 (-29.35, 23.1812) -> (-29.8983, 23.3619)
  line L335 (-29.8983, 23.3619) -> (-30.3041, 22.833)
  line L336 (-30.3041, 22.833) -> (-29.9877, 22.3502)
  line L337 (-29.9877, 22.3502) -> (-29.9869, 22.067)
  line L338 (-29.9869, 22.067) -> (-30.0818, 21.8557)
  line L339 (-30.0818, 21.8557) -> (-30.2534, 21.7002)
  line L340 (-30.2534, 21.7002) -> (-30.523, 21.6134)
  line L341 (-30.523, 21.6134) -> (-31.08, 21.7651)
  line L342 (-31.08, 21.7651) -> (-31.4576, 21.2157)
  line L343 (-31.4576, 21.2157) -> (-31.1163, 20.7501)
  line L344 (-31.1163, 20.7501) -> (-31.1007, 20.4673)
  line L345 (-31.1007, 20.4673) -> (-31.1844, 20.2514)
  line L346 (-31.1844, 20.2514) -> (-31.3476, 20.0871)
  line L347 (-31.3476, 20.0871) -> (-31.6123, 19.9863)
  line L348 (-31.6123, 19.9863) -> (-32.1765, 20.1087)
  line L349 (-32.1765, 20.1087) -> (-32.5248, 19.5403)
  line L350 (-32.5248, 19.5403) -> (-32.1596, 19.0932)
  line L351 (-32.1596, 19.0932) -> (-32.1293, 18.8116)
  line L352 (-32.1293, 18.8116) -> (-32.2016, 18.5916)
  line L353 (-32.2016, 18.5916) -> (-32.3559, 18.419)
  line L354 (-32.3559, 18.419) -> (-32.615, 18.3045)
  line L355 (-32.615, 18.3045) -> (-33.1848, 18.3972)
  line L356 (-33.1848, 18.3972) -> (-33.5029, 17.8113)
  line L357 (-33.5029, 17.8113) -> (-33.1148, 17.3839)
  line L358 (-33.1148, 17.3839) -> (-33.0698, 17.1043)
  line L359 (-33.0698, 17.1043) -> (-33.1305, 16.8808)
  line L360 (-33.1305, 16.8808) -> (-33.2756, 16.7004)
  line L361 (-33.2756, 16.7004) -> (-33.5283, 16.5724)
  line L362 (-33.5283, 16.5724) -> (-34.1021, 16.6352)
  line L363 (-34.1021, 16.6352) -> (-34.3891, 16.0335)
  line L364 (-34.3891, 16.0335) -> (-33.9792, 15.627)
  line L365 (-33.9792, 15.627) -> (-33.9196, 15.3501)
  line L366 (-33.9196, 15.3501) -> (-33.9685, 15.1238)
  line L367 (-33.9685, 15.1238) -> (-34.104, 14.936)
  line L368 (-34.104, 14.936) -> (-34.3497, 14.795)
  line L369 (-34.3497, 14.795) -> (-34.926, 14.8276)
  line L370 (-34.926, 14.8276) -> (-35.1811, 14.2117)
  line L371 (-35.1811, 14.2117) -> (-34.7505, 13.8273)
  line L372 (-34.7505, 13.8273) -> (-34.6765, 13.5539)
  line L373 (-34.6765, 13.5539) -> (-34.7135, 13.3253)
  line L374 (-34.7135, 13.3253) -> (-34.839, 13.1306)
  line L375 (-34.839, 13.1306) -> (-35.0769, 12.977)
  line L376 (-35.0769, 12.977) -> (-35.6542, 12.9794)
  line L377 (-35.6542, 12.9794) -> (-35.8767, 12.351)
  line L378 (-35.8767, 12.351) -> (-35.4266, 11.9896)
  line L379 (-35.4266, 11.9896) -> (-35.3383, 11.7204)
  line L380 (-35.3383, 11.7204) -> (-35.3633, 11.4902)
  line L381 (-35.3633, 11.4902) -> (-35.4784, 11.2893)
  line L382 (-35.4784, 11.2893) -> (-35.708, 11.1234)
  line L383 (-35.708, 11.1234) -> (-36.2846, 11.0956)
  line L384 (-36.2846, 11.0956) -> (-36.4739, 10.4564)
  line L385 (-36.4739, 10.4564) -> (-36.0055, 10.1191)
  line L386 (-36.0055, 10.1191) -> (-35.9033, 9.8549)
  line L387 (-35.9033, 9.8549) -> (-35.9162, 9.6237)
  line L388 (-35.9162, 9.6237) -> (-36.0206, 9.417)
  line L389 (-36.0206, 9.417) -> (-36.2412, 9.2394)
  line L390 (-36.2412, 9.2394) -> (-36.8156, 9.1815)
  line L391 (-36.8156, 9.1815) -> (-36.9712, 8.5332)
  line L392 (-36.9712, 8.5332) -> (-36.4858, 8.2208)
  line L393 (-36.4858, 8.2208) -> (-36.3699, 7.9624)
  line L394 (-36.3699, 7.9624) -> (-36.3706, 7.7308)
  line L395 (-36.3706, 7.7308) -> (-36.4641, 7.519)
  line L396 (-36.4641, 7.519) -> (-36.6751, 7.33)
  line L397 (-36.6751, 7.33) -> (-37.2456, 7.2421)
  line L398 (-37.2456, 7.2421) -> (-37.3671, 6.5866)
  line L399 (-37.3671, 6.5866) -> (-36.866, 6.3001)
  line L400 (-36.866, 6.3001) -> (-36.7367, 6.048)
  line L401 (-36.7367, 6.048) -> (-36.7254, 5.8167)
  line L402 (-36.7254, 5.8167) -> (-36.8077, 5.6003)
  line L403 (-36.8077, 5.6003) -> (-37.0085, 5.4005)
  line L404 (-37.0085, 5.4005) -> (-37.5736, 5.2829)
  line L405 (-37.5736, 5.2829) -> (-37.6606, 4.6219)
  line L406 (-37.6606, 4.6219) -> (-37.1452, 4.362)
  line L407 (-37.1452, 4.362) -> (-37.0029, 4.1171)
  line L408 (-37.0029, 4.1171) -> (-36.9795, 3.8867)
  line L409 (-36.9795, 3.8867) -> (-37.0503, 3.6662)
  line L410 (-37.0503, 3.6662) -> (-37.2404, 3.4562)
  line L411 (-37.2404, 3.4562) -> (-37.7986, 3.3092)
  line L412 (-37.7986, 3.3092) -> (-37.8509, 2.6446)
  line L413 (-37.8509, 2.6446) -> (-37.3226, 2.412)
  line L414 (-37.3226, 2.412) -> (-37.1677, 2.1749)
  line L415 (-37.1677, 2.1749) -> (-37.1322, 1.946)
  line L416 (-37.1322, 1.946) -> (-37.1914, 1.7221)
  line L417 (-37.1914, 1.7221) -> (-37.3702, 1.5025)
  line L418 (-37.3702, 1.5025) -> (-37.92, 1.3264)
  line L419 (-37.92, 1.3264) -> (-37.9374, 0.66)
  line L420 (-37.9374, 0.66) -> (-37.3977, 0.4554)
  line L421 (-37.3977, 0.4554) -> (-37.2306, 0.2267)
  line L422 (-37.2306, 0.2267) -> (-37.1832, 0)
  line L423 (-37.1832, 0) -> (-37.2306, -0.2267)
  line L424 (-37.2306, -0.2267) -> (-37.3977, -0.4554)
  line L425 (-37.3977, -0.4554) -> (-37.9374, -0.66)
  line L426 (-37.9374, -0.66) -> (-37.92, -1.3264)
  line L427 (-37.92, -1.3264) -> (-37.3702, -1.5025)
  line L428 (-37.3702, -1.5025) -> (-37.1914, -1.7221)
  line L429 (-37.1914, -1.7221) -> (-37.1322, -1.946)
  line L430 (-37.1322, -1.946) -> (-37.1677, -2.1749)
  line L431 (-37.1677, -2.1749) -> (-37.3226, -2.412)
  line L432 (-37.3226, -2.412) -> (-37.8509, -2.6446)
  line L433 (-37.8509, -2.6446) -> (-37.7986, -3.3092)
  line L434 (-37.7986, -3.3092) -> (-37.2404, -3.4562)
  line L435 (-37.2404, -3.4562) -> (-37.0503, -3.6662)
  line L436 (-37.0503, -3.6662) -> (-36.9795, -3.8867)
  line L437 (-36.9795, -3.8867) -> (-37.0029, -4.1171)
  line L438 (-37.0029, -4.1171) -> (-37.1452, -4.362)
  line L439 (-37.1452, -4.362) -> (-37.6606, -4.6219)
  line L440 (-37.6606, -4.6219) -> (-37.5736, -5.2829)
  line L441 (-37.5736, -5.2829) -> (-37.0085, -5.4005)
  line L442 (-37.0085, -5.4005) -> (-36.8077, -5.6003)
  line L443 (-36.8077, -5.6003) -> (-36.7254, -5.8167)
  line L444 (-36.7254, -5.8167) -> (-36.7367, -6.048)
  line L445 (-36.7367, -6.048) -> (-36.866, -6.3001)
  line L446 (-36.866, -6.3001) -> (-37.3671, -6.5866)
  line L447 (-37.3671, -6.5866) -> (-37.2456, -7.2421)
  line L448 (-37.2456, -7.2421) -> (-36.6751, -7.33)
  line L449 (-36.6751, -7.33) -> (-36.4641, -7.519)
  line L450 (-36.4641, -7.519) -> (-36.3706, -7.7308)
  line L451 (-36.3706, -7.7308) -> (-36.3699, -7.9624)
  line L452 (-36.3699, -7.9624) -> (-36.4858, -8.2208)
  line L453 (-36.4858, -8.2208) -> (-36.9712, -8.5332)
  line L454 (-36.9712, -8.5332) -> (-36.8156, -9.1815)
  line L455 (-36.8156, -9.1815) -> (-36.2412, -9.2394)
  line L456 (-36.2412, -9.2394) -> (-36.0206, -9.417)
  line L457 (-36.0206, -9.417) -> (-35.9162, -9.6237)
  line L458 (-35.9162, -9.6237) -> (-35.9033, -9.8549)
  line L459 (-35.9033, -9.8549) -> (-36.0055, -10.1191)
  line L460 (-36.0055, -10.1191) -> (-36.4739, -10.4564)
  line L461 (-36.4739, -10.4564) -> (-36.2846, -11.0956)
  line L462 (-36.2846, -11.0956) -> (-35.708, -11.1234)
  line L463 (-35.708, -11.1234) -> (-35.4784, -11.2893)
  line L464 (-35.4784, -11.2893) -> (-35.3633, -11.4902)
  line L465 (-35.3633, -11.4902) -> (-35.3383, -11.7204)
  line L466 (-35.3383, -11.7204) -> (-35.4266, -11.9896)
  line L467 (-35.4266, -11.9896) -> (-35.8767, -12.351)
  line L468 (-35.8767, -12.351) -> (-35.6542, -12.9794)
  line L469 (-35.6542, -12.9794) -> (-35.0769, -12.977)
  line L470 (-35.0769, -12.977) -> (-34.839, -13.1306)
  line L471 (-34.839, -13.1306) -> (-34.7135, -13.3253)
  line L472 (-34.7135, -13.3253) -> (-34.6765, -13.5539)
  line L473 (-34.6765, -13.5539) -> (-34.7505, -13.8273)
  line L474 (-34.7505, -13.8273) -> (-35.1811, -14.2117)
  line L475 (-35.1811, -14.2117) -> (-34.926, -14.8276)
  line L476 (-34.926, -14.8276) -> (-34.3497, -14.795)
  line L477 (-34.3497, -14.795) -> (-34.104, -14.936)
  line L478 (-34.104, -14.936) -> (-33.9685, -15.1238)
  line L479 (-33.9685, -15.1238) -> (-33.9196, -15.3501)
  line L480 (-33.9196, -15.3501) -> (-33.9792, -15.627)